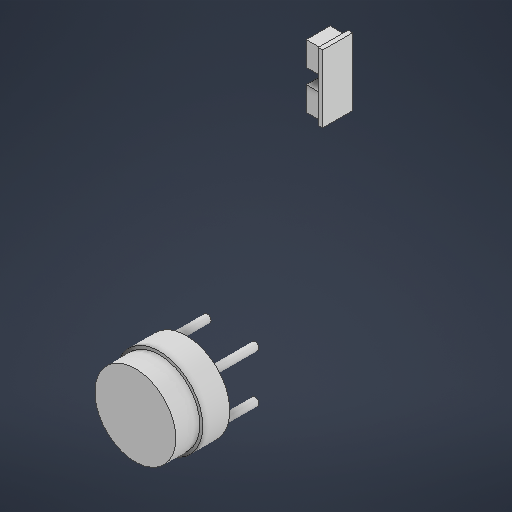
# Autodesk Inventor part: 06_Cam_Bien_YDLidar_X2_Va_HCSR05
Saved by Autodesk Inventor 2027.1 (Build 311270010, 270A)
## iProperties
Created: 2026-11-18
Part Number: 06_Cam_Bien_YDLidar_X2_Va_HCSR05
Material: Generic
Document SubType Name: Modeling
Designer: cuong
Density: 1 g/cm^3
Appearance: Default
Author: cuong
Autodesk Inventor part; units mm, degrees
ref_plane "Work Plane1" through (0, 0, 175) normal (0, 0, 1) x (1, 0, 0)
sketch "Sketch1" plane through (0, 0, 175) normal (0, 0, 1) x (1, 0, 0)
  circle A0 centre (29, 29) radius 2.5
  constraints: 1 centre point
extrude "Extrusion1" add sketch "Sketch1" along normal blind 30
ref_plane "Work Plane2" through (0, 0, 175) normal (0, 0, 1) x (1, 0, 0)
sketch "Sketch2" plane through (0, 0, 175) normal (0, 0, 1) x (1, 0, 0)
  circle A0 centre (61, 29) radius 2.5
  constraints: 1 centre point
extrude "Extrusion2" add sketch "Sketch2" along normal blind 30
ref_plane "Work Plane3" through (0, 0, 175) normal (0, 0, 1) x (1, 0, 0)
sketch "Sketch3" plane through (0, 0, 175) normal (0, 0, 1) x (1, 0, 0)
  circle A0 centre (29, 61) radius 2.5
  constraints: 1 centre point
extrude "Extrusion3" add sketch "Sketch3" along normal blind 30
ref_plane "Work Plane4" through (0, 0, 175) normal (0, 0, 1) x (1, 0, 0)
sketch "Sketch4" plane through (0, 0, 175) normal (0, 0, 1) x (1, 0, 0)
  circle A0 centre (61, 61) radius 2.5
  constraints: 1 centre point
extrude "Extrusion4" add sketch "Sketch4" along normal blind 30
ref_plane "Work Plane5" through (0, 0, 205) normal (0, 0, 1) x (1, 0, 0)
sketch "Sketch5" plane through (0, 0, 205) normal (0, 0, 1) x (1, 0, 0)
  circle A0 centre (45, 45) radius 29
  constraints: 1 centre point
extrude "Extrusion5" add sketch "Sketch5" along normal blind 18
ref_plane "Work Plane6" through (0, 0, 223) normal (0, 0, 1) x (1, 0, 0)
sketch "Sketch6" plane through (0, 0, 223) normal (0, 0, 1) x (1, 0, 0)
  circle A0 centre (45, 45) radius 27
  constraints: 1 centre point
extrude "Extrusion6" add sketch "Sketch6" along normal blind 16
ref_plane "Work Plane7" through (0, 0, 48) normal (0, 0, 1) x (1, 0, 0)
sketch "Sketch7" plane through (0, 0, 48) normal (0, 0, 1) x (1, 0, 0)
  line L0 (-4, 102.5) -> (-1, 102.5)
  line L1 (-1, 102.5) -> (-1, 147.5)
  line L2 (-1, 147.5) -> (-4, 147.5)
  line L3 (-4, 147.5) -> (-4, 102.5)
  constraints: 8 end point, 2 parallel, 1 horizontal, 1 perpendicular
extrude "Extrusion7" add sketch "Sketch7" along normal blind 20
ref_plane "Work Plane8" through (0, 0, 50) normal (0, 0, 1) x (1, 0, 0)
sketch "Sketch8" plane through (0, 0, 50) normal (0, 0, 1) x (1, 0, 0)
  line L0 (-14, 104) -> (-4, 104)
  line L1 (-4, 104) -> (-4, 120)
  line L2 (-4, 120) -> (-14, 120)
  line L3 (-14, 120) -> (-14, 104)
  constraints: 8 end point, 2 parallel, 1 horizontal, 1 perpendicular
extrude "Extrusion8" add sketch "Sketch8" along normal blind 16
ref_plane "Work Plane9" through (0, 0, 50) normal (0, 0, 1) x (1, 0, 0)
sketch "Sketch9" plane through (0, 0, 50) normal (0, 0, 1) x (1, 0, 0)
  line L0 (-14, 130) -> (-4, 130)
  line L1 (-4, 130) -> (-4, 146)
  line L2 (-4, 146) -> (-14, 146)
  line L3 (-14, 146) -> (-14, 130)
  constraints: 8 end point, 2 parallel, 1 horizontal, 1 perpendicular
extrude "Extrusion9" add sketch "Sketch9" along normal blind 16
body "Solid1"
